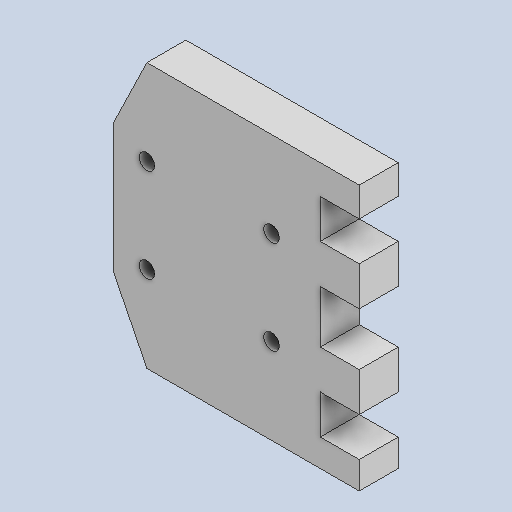
# Autodesk Inventor part: NeckSide2
Saved by Autodesk Inventor 2025.2 (Build 292293000, 293)
## iProperties
Created: 2025-06-29
Part Number: NeckSide2
Material: Generic
Document SubType Name: Modeling
Designer: ricoa
Density: 1 g/cm^3
Appearance: Default
Author: ricoa
Autodesk Inventor part; units mm, degrees
ref_plane "YZ Plane" through (0, 0, 0) normal (1, 0, 0) x (0, 1, 0)
ref_plane "XZ Plane" through (0, 0, 0) normal (0, 1, 0) x (-1, 0, 0)
ref_plane "XY Plane" through (0, 0, 0) normal (0, 0, 1) x (1, 0, 0)
sketch "Sketch1" plane through (0, 0, 0) normal (0, 0, 1) x (1, 0, 0)
  line L0 (2, -0.25) -> (2, -17) projected
  circle A0 centre (22.25, -14.5) radius 1 projected
  circle A1 centre (6.25, -14.5) radius 1 projected
  circle A2 centre (6.25, -2.5) radius 1 projected
  circle A3 centre (22.25, -2.5) radius 1 projected
  line L1 (33.5, -0.25) -> (33.5, -5.25) projected
  line L2 (28.5, -0.25) -> (33.5, -0.25) projected
  line L3 (28.5, -17) -> (33.5, -17) projected
  line L4 (33.5, -12) -> (33.5, -17) projected
  line L5 (28.5, -5.25) -> (28.5, -12) projected
  line L6 (28.5, -5.25) -> (33.5, -5.25) projected
  line L7 (28.5, -12) -> (33.5, -12) projected
  line L8 (28.5, -17) -> (26.5, -17) projected
  line L9 (28.5, -0.25) -> (26.5, -0.25) projected
  line L10 (33.5, -22) -> (33.5, -25.5) projected
  line L11 (28.5, -22) -> (33.5, -22) projected
  line L12 (28.5, -17) -> (28.5, -22) projected
  line L13 (28.5, 4.75) -> (28.5, -0.25) projected
  line L14 (28.5, 4.75) -> (33.5, 4.75) projected
  line L15 (33.5, 8.5) -> (33.5, 4.75) projected
  line L16 (2.1036, 8.5) -> (26.3964, 8.5) projected
  line L17 (26.3964, -25.5) -> (2.1036, -25.5) projected
  line L18 (6.25, 8.5) -> (2, -0.25)
  line L19 (2, -17) -> (6.25, -25.5)
  line L20 (26.3964, 8.5) -> (33.5, 8.5)
  line L21 (26.3964, -25.5) -> (33.5, -25.5)
  point P0 (0, 0)
  constraints: 8 end point, 2 point on line, 1 parallel, 1 perpendicular
extrude "Extrusion1" add sketch "Sketch1" along normal blind 5
body "Solid1"
